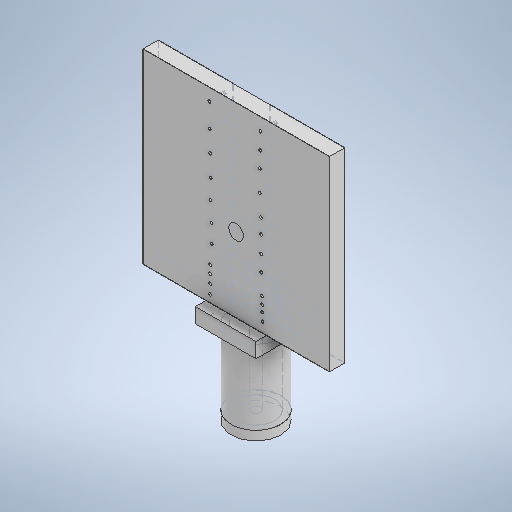
# Autodesk Inventor part: 04_coonector_plus_pcb
Saved by Autodesk Inventor 2025.3 (Build 293356000, 356)
## iProperties
Created: 2026-10-17
Part Number: 04_coonector_plus_pcb
Material: Generisch
Document SubType Name: Modeling
Designer: v.ivko
Density: 1 g/cm^3
Appearance: Vorgabe
Author: v.ivko
Autodesk Inventor part; units mm, degrees
ref_plane "YZ Plane" through (0, 0, 0) normal (1, 0, 0) x (0, 1, 0)
ref_plane "XZ Plane" through (0, 0, 0) normal (0, 1, 0) x (-1, 0, 0)
ref_plane "XY Plane" through (0, 0, 0) normal (0, 0, 1) x (1, 0, 0)
sketch "Skizze1" plane through (0, 0, 0) normal (0, 0, 1) x (1, 0, 0)
  line L0 (-10, -10) -> (10, -10)
  line L1 (10, -10) -> (10, 10)
  line L2 (10, 10) -> (-10, 10)
  line L3 (-10, 10) -> (-10, -10)
  line L4 (-10, -10) -> (10, 10) construction
  line L5 (10, -10) -> (-10, 10) construction
  point P0 (0, 0)
  dimension "d39" = 20
  dimension "d42" = 20
  constraints: 12 end point, 2 midpoint, 2 parallel, 1 horizontal, 1 perpendicular
  measures "d39" distance between parallel lines of L1 L3
  measures "d42" distance of L0.end L1.end
extrude "Extrusion1" add sketch "Skizze1" along normal blind 1.6
sketch "Skizze2" plane through (-10, -10, 0) normal (0, -1, 0) x (1, 0, 0)
  line L0 (10, 0) -> (10, -43.5363) construction
  line L1 (13.25, 2.75) -> (6.75, 2.75)
  line L2 (6.75, 2.75) -> (6.75, -3.75)
  line L3 (6.75, -3.75) -> (13.25, -3.75)
  line L4 (13.25, -3.75) -> (13.25, 2.75)
  line L5 (13.25, 2.75) -> (6.75, -3.75) construction
  line L6 (6.75, 2.75) -> (13.25, -3.75) construction
  line L7 (0, 0) -> (20, 0) projected
  circle A0 centre (10, -0.5) radius 2
  circle A1 centre (10, -0.5) radius 0.5 construction
  point P0 (13.25, 0)
  point P1 (6.75, 0)
  point P2 (8.0635, 0)
  point P3 (11.9365, 0)
  dimension "d2" = 6.5
  dimension "d3" = 6.5
  dimension "d4" = 0.5
  dimension "d27" = 4
  dimension "d30" = 1
  constraints: 14 end point, 2 centre point, 2 coincident, 2 midpoint, 2 parallel, 1 horizontal, 1 perpendicular, 1 point on line, 1 vertical
  measures "d2" distance of L2.end L3.end
  measures "d3" distance of L1.end L2.end
  measures "d4" distance from line of L7 point (10, -0.5)
  measures "d27" diameter of A0
  measures "d30" diameter of A1
extrude "Extrusion2" add sketch "Skizze2" along normal blind 1.6 separate body contours L4 L7 A0 L2 L1 | L4 L3 L2 L7 A0
sketch "Skizze3" plane through (-10, -11.6, 0) normal (0, -1, 0) x (1, 0, 0)
  circle A0 centre (10, -0.5) radius 2 projected
  circle A1 centre (10, -0.5) radius 2.675
  point P0 (10, 0)
  dimension "d28" = 5.35
  constraints: 1 centre point, 1 coincident
  measures "d28" diameter of A1
extrude "Extrusion3" add sketch "Skizze3" along normal blind 8 bodies 2
sketch "Skizze4" plane through (0, -19.6, -0.5) normal (0, -1, 0) x (1, 0, 0)
  circle A0 centre (0, 0) radius 0.5
  circle A1 centre (0, 0) radius 2 projected
  point P0 (0, 0.5)
  dimension "d29" = 1
  constraints: 1 centre point
  measures "d29" diameter of A0
extrude "Extrusion4" add sketch "Skizze4" against normal up to surface (9.6 mm away) separate body
sketch "Skizze5" plane through (0, -19.6, -0.5) normal (0, -1, 0) x (1, 0, 0)
  circle A0 centre (0, 0) radius 0.5
  point P0 (0, 0.5)
  dimension "d31" = 1
  constraints: 1 centre point
  measures "d31" diameter of A0
extrude "Extrusion5" add sketch "Skizze5" against normal up to surface (9.6 mm away) separate body
sketch "Skizze6" plane through (0, -10, -0.5) normal (0, 1, 0) x (1, 0, 0)
  circle A0 centre (0, 0) radius 0.5 projected
  point P0 (0, -0.5)
extrude "Extrusion6" add sketch "Skizze6" along normal blind 4 bodies 4
sketch "Skizze7" plane through (-10, -10, 0) normal (0, 1, 0) x (1, 0, 0)
  line L0 (6.75, 0.035) -> (7.75, 0.035)
  line L1 (7.75, 0.035) -> (7.75, 1.035)
  line L2 (7.75, 1.035) -> (6.75, 1.035)
  line L3 (6.75, 1.035) -> (6.75, 0.035)
  line L4 (6.75, 0.035) -> (7.75, 1.035) construction
  line L5 (7.75, 0.035) -> (6.75, 1.035) construction
  circle A0 centre (10, 0.5) radius 0.5 projected
  line L6 (10, 0.5) -> (10, 3.9078) construction
  line L7 (20, 0) -> (0, 0) projected
  line L8 (6.75, -2.75) -> (6.75, 3.75) projected
  line L9 (13.25, 0.035) -> (12.25, 0.035)
  line L10 (12.25, 0.035) -> (12.25, 1.035)
  line L11 (12.25, 1.035) -> (13.25, 1.035)
  line L12 (13.25, 1.035) -> (13.25, 0.035)
  point P0 (10, 0)
  point P1 (7.25, 0.535)
  dimension "d15" = 1
  dimension "d16" = 1
  dimension "d17" = 0.035
  constraints: 22 end point, 4 symmetric about line, 2 midpoint, 2 parallel, 1 collinear, 1 horizontal, 1 perpendicular, 1 vertical
  measures "d15" distance of L1.end L2.end
  measures "d16" distance of L2.end L0.start
  measures "d17" distance between parallel lines of L7 L0
extrude "Extrusion7" add sketch "Skizze7" along normal blind 4 contours L3 L2 L1 L0 | L9 L10 L11 L12 bodies 2
sketch "Skizze8" plane through (0, 0, 0) normal (0, 0, -1) x (-1, 0, 0)
  line L0 (1, -2) -> (-1, -2)
  line L1 (-1, -2) -> (-1, -10)
  line L2 (-1, -10) -> (1, -10)
  line L3 (1, -10) -> (1, -2)
  line L4 (1, -2) -> (-1, -10) construction
  line L5 (-1, -2) -> (1, -10) construction
  line L6 (10, -10) -> (-10, -10) projected
  line L7 (2, 0) -> (4, 0)
  line L8 (4, 0) -> (4, -10)
  line L9 (4, -10) -> (2, -10)
  line L10 (2, -10) -> (2, 0)
  line L11 (10, 10) -> (10, -10) projected
  line L12 (-10, -10) -> (-10, 10) projected
  line L13 (0, 0) -> (0, -30.5211) construction
  line L14 (0, -6) -> (0, -10) construction
  line L15 (3, -10) -> (3, 0) construction
  line L16 (-2, -10) -> (-2, 0)
  line L17 (-2, 0) -> (-4, 0)
  line L18 (-4, 0) -> (-4, -10)
  line L19 (-4, -10) -> (-2, -10)
  line L20 (-2, -10) -> (-10, -10)
  line L21 (-10, -10) -> (-10, 10)
  line L22 (-10, 10) -> (-2, 10)
  line L23 (-2, 10) -> (-2, -10)
  line L24 (2, -10) -> (10, -10)
  line L25 (10, -10) -> (10, 10)
  line L26 (10, 10) -> (2, 10)
  line L27 (2, 10) -> (2, -10)
  point P0 (2, -10)
  point P1 (4, -10)
  point P2 (-4, -10)
  point P3 (-2, -10)
  point P4 (2, 0)
  point P5 (-2, 0)
  dimension "d20" = 2
  dimension "d21" = 8
  dimension "d40" = 2
  dimension "d41" = 10
  constraints: 50 end point, 6 parallel, 5 midpoint, 4 symmetric about line, 3 horizontal, 3 perpendicular, 2 collinear, 1 vertical
  measures "d20" distance between parallel lines of L1 L3
  measures "d21" distance of L0.end L1.end
  measures "d40" distance between parallel lines of L13 L10
  measures "d41" distance of L7.end L8.end
extrude "Extrusion8" add sketch "Skizze8" along normal blind 0.035 separate body
sketch "Skizze9" plane through (0, 0, 1.6) normal (0, 0, 1) x (1, 0, 0)
  line L0 (10, -10) -> (10, 10) projected
  line L1 (10, 10) -> (-10, 10) projected
  line L2 (-10, 10) -> (-10, -10) projected
  line L3 (-10, -10) -> (10, -10) projected
  point P0 (0, 0)
extrude "Extrusion9" add sketch "Skizze9" along normal blind 0.035 separate body
sketch "Skizze10" plane through (0, -6, -0.5) normal (0, 1, 0) x (1, 0, 0)
  circle A0 centre (0, 0) radius 0.5 projected
  line L0 (1, -0.465) -> (-1, -0.465) projected
  line L1 (-0.5, 0) -> (0.5, 0)
  line L2 (0.5, 0) -> (0.5, -0.465)
  line L3 (0.5, -0.465) -> (-0.5, -0.465)
  line L4 (-0.5, -0.465) -> (-0.5, 0)
  line L5 (0.5, 0) -> (0.5, 0.1708) construction
  point P0 (0, -0.5)
  constraints: 10 end point, 2 parallel, 2 point on circle, 1 collinear, 1 horizontal, 1 perpendicular, 1 point on line, 1 tangent, 1 vertical
extrude "Extrusion10" add sketch "Skizze10" against normal blind 2 separate body contours L2 L0 A0 | A0 L0 L1 | A0 L0 L4
sketch "Skizze11" plane through (0, -19.6, -0.5) normal (0, -1, 0) x (1, 0, 0)
  line L0 (-0.5, 0) -> (0.5, 0) projected
  circle A0 centre (0, 0) radius 2.675
  point P0 (0, 0.5)
  constraints: 1 centre point, 1 midpoint
extrude "Extrusion11" add sketch "Skizze11" along normal blind 1 separate body
sketch "Skizze12" plane through (0, 0, -0.035) normal (0, 0, -1) x (-1, 0, 0)
  line L0 (1, -2) -> (-1, -2) projected
  circle A0 centre (0, -2) radius 0.5
  point P0 (0, 0)
  dimension "d36" = 1
  constraints: 1 centre point, 1 midpoint
  measures "d36" diameter of A0
extrude "Extrusion12" add sketch "Skizze12" against normal up to surface (1.67 mm away) draft 10 separate body
sketch "Skizze13" plane through (0, 0, -0.035) normal (0, 0, -1) x (-1, 0, 0)
  circle A0 centre (-2.7529, -6.587) radius 0.15
  circle A1 centre (-2.7808, -8.0634) radius 0.15
  circle A2 centre (-2.7808, -7.367) radius 0.15
  circle A3 centre (-2.8226, -8.927) radius 0.15
  circle A4 centre (2.7907, -6.437) radius 0.15
  circle A5 centre (2.8047, -8.2134) radius 0.15
  circle A6 centre (2.8047, -7.2973) radius 0.15
  circle A7 centre (2.8047, -9.2195) radius 0.15
  circle A8 centre (-2.6726, -4.428) radius 0.15
  circle A9 centre (-2.6726, -2.7008) radius 0.15
  circle A10 centre (-2.6726, -0.904) radius 0.15
  circle A11 centre (-2.6428, 0.6611) radius 0.15
  circle A12 centre (-2.5251, 2.8592) radius 0.15
  circle A13 centre (-2.5251, 5.1531) radius 0.15
  circle A14 centre (-2.5739, 6.8725) radius 0.15
  circle A15 centre (-2.604, 8.6462) radius 0.15
  circle A16 centre (2.6269, -4.4309) radius 0.15
  circle A17 centre (2.6419, -2.5069) radius 0.15
  circle A18 centre (2.7472, -0.4326) radius 0.15
  circle A19 centre (2.7321, 1.6567) radius 0.15
  circle A20 centre (2.8073, 3.8964) radius 0.15
  circle A21 centre (2.8373, 6.151) radius 0.15
  circle A22 centre (2.8824, 8.6763) radius 0.15
  dimension "d45" = 0.3
  dimension "d46" = 0.3
  dimension "d47" = 0.3
  dimension "d48" = 0.3
  dimension "d49" = 0.3
  dimension "d50" = 0.3
  dimension "d51" = 0.3
  dimension "d52" = 0.3
  dimension "d53" = 0.3
  dimension "d54" = 0.3
  dimension "d55" = 0.3
  dimension "d56" = 0.3
  dimension "d57" = 0.3
  dimension "d58" = 0.3
  dimension "d59" = 0.3
  dimension "d60" = 0.3
  dimension "d61" = 0.3
  dimension "d62" = 0.3
  dimension "d63" = 0.3
  dimension "d64" = 0.3
  dimension "d65" = 0.3
  dimension "d66" = 0.3
  dimension "d67" = 0.3
  constraints: 23 centre point
  measures "d45" diameter of A0
  measures "d46" diameter of A1
  measures "d47" diameter of A2
  measures "d48" diameter of A3
  measures "d49" diameter of A4
  measures "d50" diameter of A5
  measures "d51" diameter of A6
  measures "d52" diameter of A7
  measures "d53" diameter of A8
  measures "d54" diameter of A9
  measures "d55" diameter of A10
  measures "d56" diameter of A11
  measures "d57" diameter of A12
  measures "d58" diameter of A13
  measures "d59" diameter of A14
  measures "d60" diameter of A15
  measures "d61" diameter of A16
  measures "d62" diameter of A17
  measures "d63" diameter of A18
  measures "d64" diameter of A19
  measures "d65" diameter of A20
  measures "d66" diameter of A21
  measures "d67" diameter of A22
extrude "Extrusion13" cut sketch "Skizze13" against normal blind 10 bodies 5 1 6
